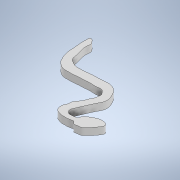
# Autodesk Inventor part: serpisor
Saved by Autodesk Inventor 2022.6 (Build 266554000, 554)
## iProperties
Created: 2024-11-29
Part Number: serpisor
Material: Generic
Document SubType Name: Modeling
Designer: Dragos Macovei
Density: 1 g/cm^3
Appearance: Default
Author: Dragos Macovei
Autodesk Inventor part; units mm, degrees
ref_plane "YZ Plane" through (0, 0, 0) normal (1, 0, 0) x (0, 1, 0)
ref_plane "XZ Plane" through (0, 0, 0) normal (0, 1, 0) x (-1, 0, 0)
ref_plane "XY Plane" through (0, 0, 0) normal (0, 0, 1) x (1, 0, 0)
sketch "Sketch1" plane through (0, 0, 0) normal (0, 1, 0) x (-1, 0, 0)
  line L0 (0, 0) -> (40, 0)
  line L1 (40, 0) -> (40, 40)
  line L2 (40, 40) -> (0, 40)
  line L3 (0, 40) -> (0, 0)
  line L4 (-192.1675, 355.8003) -> (214.2325, 355.8003) construction
  line L5 (214.2325, 355.8003) -> (214.2325, -186.0664) construction
  line L6 (214.2325, -186.0664) -> (-192.1675, -186.0664) construction
  line L7 (-192.1675, -186.0664) -> (-192.1675, 355.8003) construction
  spline S0 degree 5 poles (8.8993, 37.4554) (8.8, 37.5769) (8.6502, 37.8006) (8.4429, 38.1145) (7.8896, 38.47) (6.8727, 37.9202) (6.0885, 38.0314) (4.9189, 37.908) (3.9882, 36.4293) (3.1962, 35.9148) (0.6593, 32.6666) (0.8532, 31.921) (1.3373, 31.2901) (1.7858, 31.1053) (2.9805, 30.7644) (3.8347, 30.8637) (4.9208, 30.9078) (6.0826, 31.6481) (7.0797, 31.8188) (7.8812, 32.8674) (8.8201, 33.0265) (9.0939, 33.8803) (9.569, 34.3153) (9.1975, 35.353) (10.7547, 35.2941) (11.0454, 35.3947) (12.5597, 35.5349) (13.3796, 35.5714) (14.0392, 34.5109) (14.791, 33.7797) (13.3527, 31.1424) (12.6434, 29.3783) (11.349, 25.9719) (9.9602, 24.1505) (9.3137, 21.5366) (11.0141, 19.1241) (11.8377, 16.5769) (15.2686, 15.5346) (16.0728, 15.6482) (21.0107, 16.1343) (22.6691, 15.8708) (25.2412, 16.5026) (27.3367, 16.3947) (29.8477, 16.6517) (31.087, 15.2845) (32.7899, 15.0333) (32.9394, 12.8953) (33.4677, 10.7842) (33.7636, 9.5623) (34.8436, 6.8277) (33.485, 4.657) (35.0715, 3.8619) (35.3149, 2.8739) (36.2383, 2.8108) (36.9666, 2.8571) (36.519, 4.4032) (36.8892, 4.5075) (36.6215, 8.0856) (36.5699, 7.6916) (36.4391, 10.0781) (36.2759, 11.0653) (36.43, 12.6742) (35.7221, 13.8215) (35.8628, 14.983) (34.6762, 16.613) (34.5885, 17.4671) (33.7031, 18.2789) (33.4526, 18.6247) (32.4909, 19.1302) (32.1061, 19.6171) (31.0092, 19.8648) (30.35, 20.1519) (29.0163, 19.8404) (27.1025, 20.2352) (24.0529, 19.4711) (23.177, 19.901) (20.8833, 19.4054) (19.146, 19.3972) (17.5351, 19.7906) (16.1258, 19.2956) (14.5073, 19.2626) (13.8121, 20.6554) (12.7066, 21.4029) (13.2554, 22.5821) (13.2238, 23.9211) (13.726, 25.03) (14.4802, 25.878) (14.5379, 27.1962) (15.372, 28.4052) (16.0477, 29.1316) (17.277, 30.6183) (16.3515, 31.8228) (17.7625, 33.0939) (17.6008, 34.4939) (17.6273, 34.9231) (17.217, 36.2266) (16.7968, 36.4767) (16.1797, 36.9486) (15.2127, 37.2236) (14.2971, 37.481) (13.6652, 37.6229) (12.7524, 37.2731) (11.6351, 37.7655) (10.7735, 37.1952) (10.1085, 37.3804) (9.5327, 36.973) (9.1752, 37.1558) (8.9941, 37.3397) (8.8993, 37.4554) knots 0 0 0 0 0 0 0.008299 0.014184 0.021714 0.02987 0.039146 0.05001 0.060626 0.070737 0.080053 0.088583 0.095611 0.103087 0.111384 0.120343 0.129484 0.138465 0.147085 0.155064 0.162577 0.169838 0.177062 0.184757 0.192701 0.200837 0.209002 0.217985 0.227981 0.23958 0.252381 0.266094 0.280242 0.29429 0.307847 0.320982 0.334963 0.348834 0.362459 0.376012 0.389734 0.402238 0.414015 0.425426 0.436677 0.447699 0.459453 0.471645 0.483547 0.494465 0.504471 0.512704 0.520048 0.52714 0.535516 0.544104 0.553682 0.563796 0.574252 0.583857 0.593849 0.603995 0.613851 0.623265 0.632073 0.640468 0.64804 0.655434 0.662755 0.670489 0.679174 0.689347 0.700038 0.711621 0.723812 0.735629 0.746599 0.757449 0.767932 0.777856 0.78739 0.796793 0.806077 0.81513 0.824314 0.833709 0.843055 0.85264 0.86238 0.872399 0.882256 0.891644 0.900622 0.908946 0.916498 0.923986 0.931675 0.939083 0.946819 0.95501 0.963143 0.971045 0.978887 0.986411 0.992087 1 1 1 1 1 1
  point P0 (7.98, 38.2435)
  point P1 (7.0606, 38.0934)
  point P2 (6.1975, 37.9808)
  point P3 (5.2781, 37.7744)
  point P4 (4.265, 36.9113)
  point P5 (2.8577, 35.354)
  point P6 (0.9252, 32.2957)
  point P7 (1.0753, 31.6953)
  point P8 (1.3755, 31.3576)
  point P9 (1.7883, 31.1324)
  point P10 (2.7264, 30.8885)
  point P11 (3.7584, 30.851)
  point P12 (4.8466, 31.0386)
  point P13 (6.0849, 31.5452)
  point P14 (7.1169, 32.0705)
  point P15 (8.0738, 32.7835)
  point P16 (8.768, 33.2714)
  point P17 (9.162, 33.853)
  point P18 (9.3872, 34.4159)
  point P19 (9.556, 35.0351)
  point P20 (10.4004, 35.3165)
  point P21 (11.2072, 35.3915)
  point P22 (12.4455, 35.5041)
  point P23 (13.2898, 35.354)
  point P24 (13.8902, 34.7724)
  point P25 (14.303, 33.9468)
  point P26 (13.8527, 32.0893)
  point P27 (12.6707, 29.4062)
  point P28 (11.2635, 26.1978)
  point P29 (10.1002, 23.8337)
  point P30 (9.8562, 21.6009)
  point P31 (10.8507, 19.1055)
  point P32 (12.4617, 16.8959)
  point P33 (14.7222, 15.8194)
  point P34 (16.6059, 15.7118)
  point P35 (20.5887, 15.9809)
  point P36 (23.0645, 16.0886)
  point P37 (25.3249, 16.3577)
  point P38 (27.6931, 16.4653)
  point P39 (29.8459, 16.1962)
  point P40 (31.2991, 15.4427)
  point P41 (32.3755, 14.6892)
  point P42 (32.9676, 13.1284)
  point P43 (33.3981, 11.0832)
  point P44 (33.8825, 9.3609)
  point P45 (34.2593, 6.4546)
  point P46 (34.3045, 4.4844)
  point P47 (35.0805, 3.4942)
  point P48 (35.6158, 2.9723)
  point P49 (36.2447, 2.8519)
  point P50 (36.6461, 3.0392)
  point P51 (36.7121, 3.8108)
  point P52 (36.7247, 4.7568)
  point P53 (36.6493, 7.3883)
  point P54 (36.5589, 8.2386)
  point P55 (36.4323, 9.7943)
  point P56 (36.3418, 11.2234)
  point P57 (36.2333, 12.5983)
  point P58 (35.9077, 13.8103)
  point P59 (35.5639, 15.0947)
  point P60 (34.782, 16.7105)
  point P61 (34.2893, 17.6412)
  point P62 (33.7418, 18.2708)
  point P63 (33.3038, 18.654)
  point P64 (32.6195, 19.1193)
  point P65 (32.0173, 19.5299)
  point P66 (31.2234, 19.8311)
  point P67 (30.4844, 20)
  point P68 (29.4715, 20)
  point P69 (27.309, 20)
  point P70 (24.3253, 19.7216)
  point P71 (22.8198, 19.6942)
  point P72 (20.8762, 19.5026)
  point P73 (19.0148, 19.5026)
  point P74 (17.4546, 19.5847)
  point P75 (15.949, 19.3931)
  point P76 (14.6351, 19.6394)
  point P77 (13.6496, 20.6249)
  point P78 (13.0748, 21.5282)
  point P79 (13.1295, 22.5684)
  point P80 (13.3485, 23.8823)
  point P81 (13.7865, 24.9773)
  point P82 (14.3066, 25.9354)
  point P83 (14.6898, 27.1124)
  point P84 (15.3194, 28.2621)
  point P85 (16.1133, 29.2476)
  point P86 (16.7976, 30.5889)
  point P87 (16.8797, 31.8754)
  point P88 (17.5093, 33.381)
  point P89 (17.6188, 34.4759)
  point P90 (17.5093, 35.1876)
  point P91 (17.1534, 36.0909)
  point P92 (16.7702, 36.5015)
  point P93 (16.1954, 36.8574)
  point P94 (15.2373, 37.2132)
  point P95 (14.334, 37.4554)
  point P96 (13.6647, 37.5175)
  point P97 (12.7772, 37.4554)
  point P98 (11.59, 37.5175)
  point P99 (10.6564, 37.3216)
  point P100 (9.9763, 37.2063)
  point P101 (9.3654, 37.1256)
  dimension "d0" = 40
  dimension "d1" = 40
  constraints: 8 end point, 2 parallel, 1 horizontal, 1 perpendicular, 106 other
  measures "d0" distance of L2.end L1.end
  measures "d1" distance of L1.end L0.end
extrude "Extrusion1" add sketch "Sketch1" along normal blind 3 contours S0
body "Solid1"
